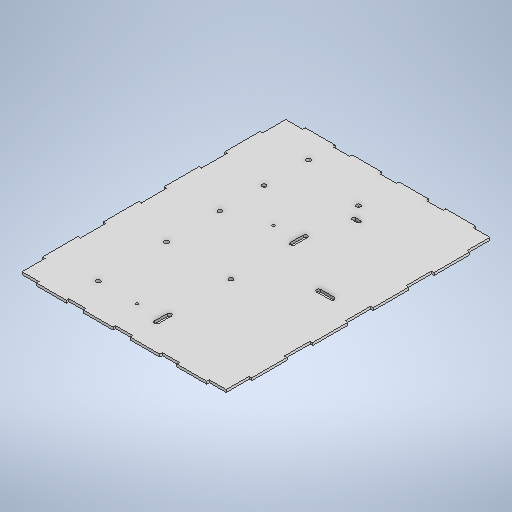
# Autodesk Inventor part: Tapa_orquesta
Saved by Autodesk Inventor 2025.2 (Build 292293000, 293)
## iProperties
Created: 2025-05-14
Part Number: Tapa_orquesta
Material: Generic
Document SubType Name: Modeling
Designer: laura
Density: 1 g/cm^3
Appearance: Default
ancho: 220.000 mm
largo: 310.000 mm
d_fila1: 40.000 mm
d_fila2: 10.000 mm
d_fila3: 66.000 mm
Author: laura
Autodesk Inventor part; units mm, degrees
ref_plane "YZ Plane" through (0, 0, 0) normal (1, 0, 0) x (0, 1, 0)
ref_plane "XZ Plane" through (0, 0, 0) normal (0, 1, 0) x (-1, 0, 0)
ref_plane "XY Plane" through (0, 0, 0) normal (0, 0, 1) x (1, 0, 0)
sketch "Sketch1" plane through (0, 0, 0) normal (0, 1, 0) x (-1, 0, 0)
  line L0 (120, 155) -> (-120, 155)
  line L1 (-120, 155) -> (-120, -155)
  line L2 (-120, -155) -> (120, -155)
  line L3 (120, -155) -> (120, 155)
  line L4 (0, 155) -> (0, -155) construction
  line L5 (65.5, 40) -> (65.5, -155) construction
  line L6 (120, 80) -> (0, 80) construction
  line L7 (-10.5, 155) -> (-10.5, -155) construction
  line L8 (-80, 155) -> (-80, -155) construction
  line L9 (65.5, 40) -> (-10.5, 40) construction
  line L10 (65.5, 120) -> (-10.5, 120) construction
  line L11 (0, -75) -> (-10.5, -75) construction
  line L12 (120, -75) -> (0, -75) construction
  point P0 (0, 0)
  point P1 (65.5, -75)
  point P2 (65.5, -23)
  point P3 (65.5, -127)
  point P4 (-80, 0)
  point P5 (-10.5, -110)
  point P6 (-10.5, -40)
  point P7 (120, 0)
  point P8 (0, 0)
  dimension "d0" = 310
  dimension "d1" = 240
  dimension "d5" = 52
  dimension "d6" = 75
  dimension "d20" = 35
  dimension "d21" = 40
  dimension "d22" = 80
  dimension "d69" = 69.5
  dimension "d70" = 76
  dimension "d71" = 40
  constraints: 27 end point, 18 point on line, 5 midpoint, 5 perpendicular, 3 horizontal, 3 symmetric about line, 2 parallel, 1 coincident, 1 collinear
  measures "d0" distance of L0.end L1.end
  measures "d1" distance of L1.end L2.end
  measures "d5" distance of point (65.5, -23) point (65.5, -75)
  measures "d6" distance between parallel lines of L0 L6
  measures "d20" distance from line of point (-10.5, -110) L11
  measures "d21" vertical distance of point (120, 0) L5.start
  measures "d22" distance between parallel lines of L2 L12
  measures "d69" distance between parallel lines of L7 L8
  measures "d70" distance between parallel lines of L5 L7
  measures "d71" distance between parallel lines of L8 L1
extrude "Extrusion1" add sketch "Sketch1" against normal blind 3
hole "Hole1" at (-65.5, 0, -75) at (-65.5, 0, -23) at (-65.5, 0, -127) at (80, 0, 0) at (10.5, 0, 40) at (10.5, 0, -110) at (10.5, 0, -40) at (10.5, 0, 120) at (-65.5, 0, 40) at (-65.5, 0, 120) direction (0, -1, 0) diameter 5 end through all
sketch "Sketch2" plane through (0, 0, 0) normal (0, 1, 0) x (1, 0, 0)
  circle A0 centre (10.5, -120) radius 2.5 projected
  circle A1 centre (10.5, 40) radius 2.5 projected
  line L0 (10.5, 40) -> (-19.5, 40) construction
  line L1 (10.5, -120) -> (-19.5, -120) construction
  line L2 (-19.5, -120) -> (-19.5, 40) construction
  circle A2 centre (-19.5, -120) radius 1.5
  circle A3 centre (-19.5, 40) radius 1.5
  point P0 (0, 0)
  dimension "d24" = 30
  dimension "d26" = 3
  constraints: 6 end point, 2 centre point, 2 coincident, 2 horizontal, 1 equal radius, 1 vertical
  measures "d24" distance of L1.start L1.end
  measures "d26" diameter of A2
extrude "Extrusion2" cut sketch "Sketch2" against normal through all contours A2 | A3
sketch "Sketch3" plane through (0, 0, 0) normal (0, 1, 0) x (1, 0, 0)
  line L0 (8, -127.5) -> (8, -112.5)
  circle A0 centre (10.5, -120) radius 2.5 projected
  line L1 (10.5, -120) -> (8, -120) construction
  line L2 (10.5, -127.5) -> (10.5, -112.5) construction
  arc A1 (8, -127.5) -> (13, -127.5) centre (10.5, -127.5) ccw
  line L3 (8, -127.5) -> (13, -127.5) construction
  line L4 (13, -127.5) -> (13, -112.5)
  arc A2 (13, -112.5) -> (8, -112.5) centre (10.5, -112.5) ccw
  line L5 (8, 32.5) -> (8, 47.5)
  arc A3 (13, 47.5) -> (8, 47.5) centre (10.5, 47.5) ccw
  line L6 (13, 47.5) -> (13, 32.5)
  arc A4 (8, 32.5) -> (13, 32.5) centre (10.5, 32.5) ccw
  line L7 (10.5, 30) -> (10.5, 50) construction
  line L8 (13, 40) -> (8, 40) construction
  circle A5 centre (10.5, 40) radius 2.5 projected
  line L9 (73.5, -2.5) -> (89.5, -2.5)
  arc A6 (89.5, -2.5) -> (89.5, 2.5) centre (89.5, 0) ccw
  line L10 (89.5, 2.5) -> (73.5, 2.5)
  arc A7 (73.5, 2.5) -> (73.5, -2.5) centre (73.5, 0) ccw
  circle A8 centre (80, 0) radius 2.5 projected
  line L11 (120, 155) -> (-120, 155) projected
  line L12 (120, -155) -> (120, 155) projected
  line L13 (89.5, 0) -> (73.5, 0) construction
  line L14 (21, 94) -> (27, 94) construction
  line L15 (21, 96) -> (27, 96)
  arc A9 (27, 92) -> (27, 96) centre (27, 94) ccw
  line L16 (27, 92) -> (21, 92)
  arc A10 (21, 96) -> (21, 92) centre (21, 94) ccw
  point P0 (0, 0)
  point P1 (24, 94)
  point P2 (81.5, 0)
  point P3 (24, 94)
  dimension "d29" = 2.5
  dimension "d30" = 15
  dimension "d33" = 15
  dimension "d34" = 2.5
  dimension "d36" = 16
  dimension "d37" = 61
  dimension "d38" = 96
  dimension "d73" = 0
  dimension "d74" = 5
  dimension "d75" = 1.5
  dimension "d76" = 4
  dimension "d77" = 6
  constraints: 30 end point, 18 point on circle, 12 tangent, 8 centre point, 7 midpoint, 6 coincident, 6 horizontal, 3 vertical, 2 symmetric about line, 1 parallel, 1 perpendicular, 1 other
  measures "d29" distance from line of L0 L1.start
  measures "d30" distance of L0.start L0.end
  measures "d33" distance of A3.centre A4.centre
  measures "d34" distance between parallel lines of L7 L5
  measures "d36" distance of L13.start L13.end
  measures "d37" distance from line of L11 point (24, 94)
  measures "d38" distance from line of L12 point (24, 94)
  measures "d73" vertical distance of A8.centre point (81.5, 0)
  measures "d74" distance between parallel lines of L9 L10
  measures "d75" distance of A8.centre point (81.5, 0)
  measures "d76" distance between parallel lines of L16 L15
  measures "d77" distance of L14.end L14.start
extrude "Extrusion3" cut sketch "Sketch3" against normal through all contours L0 A0 L4 A1 | L0 A2 L4 A0 | L5 A5 L6 A4 | L5 A3 L6 A5 | A5 | A7 L10 A8 L9 | A8 L10 A6 L9 | L15 A9 L16 A10
sketch "Sketch4" plane through (0, 0, 0) normal (0, 1, 0) x (1, 0, 0)
  line L0 (-120, -155) -> (-120, 155) projected
  line L1 (-100, -158) -> (-65, -158)
  line L2 (-65, -158) -> (-65, -155)
  line L3 (-65, -155) -> (-45, -155)
  line L4 (120, -155) -> (-120, -155) projected
  line L5 (-45, -155) -> (-45, -158)
  line L6 (-45, -158) -> (-10, -158)
  line L7 (-10, -158) -> (-10, -155)
  line L8 (-10, -155) -> (10, -155)
  line L9 (10, -158) -> (10, -155)
  line L10 (10, -158) -> (45, -158)
  line L11 (45, -158) -> (45, -155)
  line L12 (45, -155) -> (65, -155)
  line L13 (65, -158) -> (100, -158)
  line L14 (100, -158) -> (100, -155)
  line L15 (100, -155) -> (120, -155)
  line L16 (65, -158) -> (65, -155)
  line L17 (-100, -158) -> (-100, -155)
  line L18 (120, 155) -> (-120, 155) projected
  line L19 (120, -128) -> (123, -128)
  line L20 (123, -128) -> (123, -86.5)
  line L21 (123, -86.5) -> (120, -86.5)
  line L22 (120, 155) -> (120, -155) projected
  line L23 (120, -56.5) -> (123, -56.5)
  line L24 (123, -56.5) -> (123, -15)
  line L25 (123, -15) -> (120, -15)
  line L26 (120, 15) -> (123, 15)
  line L27 (123, 15) -> (123, 56.5)
  line L28 (123, 56.5) -> (120, 56.5)
  line L29 (120, 86.5) -> (123, 86.5)
  line L30 (123, 86.5) -> (123, 128)
  line L31 (123, 128) -> (120, 128)
  point P0 (0, 0)
  dimension "d40" = 20
  dimension "d41" = 20
  dimension "d42" = 20
  dimension "d43" = 20
  dimension "d46" = 20
  dimension "d47" = 3
  dimension "d58" = 30
  dimension "d60" = 30
  dimension "d61" = 30
  dimension "d64" = 30
  dimension "d65" = 3
  dimension "d66" = 27
  constraints: 56 end point, 10 point on line, 9 perpendicular, 7 collinear, 5 vertical, 3 parallel, 1 horizontal, 18 other
  measures "d40" distance between parallel lines of L17 L0
  measures "d41" distance between parallel lines of L5 L2
  measures "d42" distance between parallel lines of L9 L7
  measures "d43" distance between parallel lines of L16 L11
  measures "d46" distance from line of L15.end L14
  measures "d58" distance between parallel lines of L19 L13
  measures "d60" distance between parallel lines of L26 L25
  measures "d61" distance between parallel lines of L29 L28
  measures "d64" distance between parallel lines of L23 L21
  measures "d66" distance between parallel lines of L18 L31
extrude "Extrusion4" add sketch "Sketch4" against normal blind 3 contours L4 L2 L1 L17 | L4 L7 L6 L5 | L4 L11 L10 L9 | L4 L14 L13 L16
mirror "Mirror1" about plane through (0, 0, 0) normal (0, 0, 1) of "Extrusion4"
extrude "Extrusion5" add sketch "Sketch4" against normal blind 3 contours L31 L30 L29 L22 | L28 L27 L26 L22 | L25 L24 L23 L22 | L21 L20 L19 L22
mirror "Mirror2" about plane through (0, 0, 0) normal (1, 0, 0) of "Extrusion5"
equation "\"d0\" = largo"
equation "\"ancho\" = 220"
equation "\"largo\" = 310"
equation "\"d_fila1\" = 40"
equation "\"d_fila2\" = 10"
equation "\"d_fila3\" = 66"
body "Solid1"
